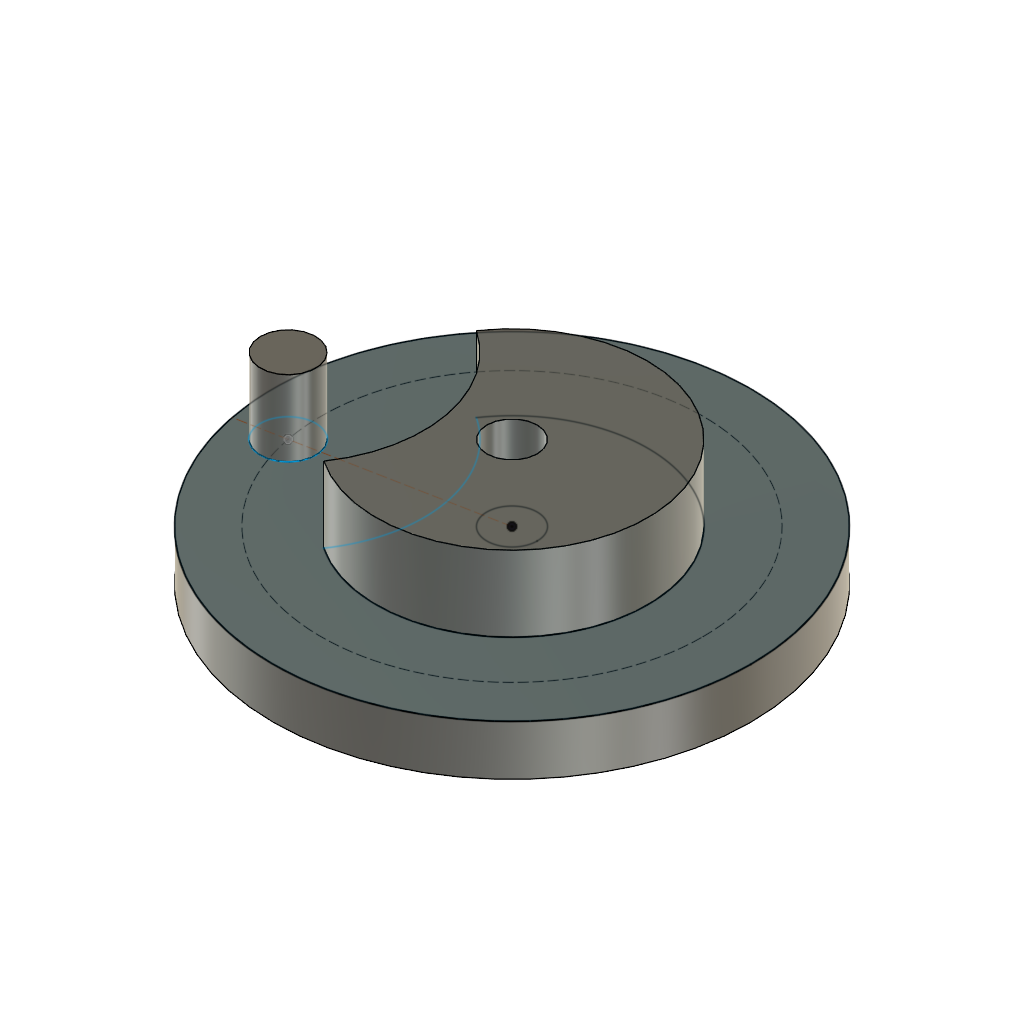
Geneva_Mechanism_Assembly (Autodesk Fusion 360 archive; units mm, degrees)
design "Genevamechfina;"
part number: 2026-10-26-18-54-31-183
Autodesk Fusion 360 part; units mm, degrees
sketch "Sketch1" plane through (0, 0, 0) normal (0, 0, 1) x (1, 0, 0)
  circle A0 centre (0, 0) radius 47.5
  line L0 (0, 0) -> (-46.627, -9.0648) construction
  circle A1 centre (0, 0) radius 38 construction
  circle A2 centre (-37.3016, -7.2518) radius 5.5
  arc A3 (-14.9899, -22.4567) -> (-22.3117, 15.2048) centre (-37.3016, -7.2518) ccw
  arc A4 (-14.9899, -22.4567) -> (-22.3117, 15.2048) centre (0, 0) ccw
  circle A5 centre (0, 0) radius 5
  dimension "d1" = 95
  dimension "d2" = 54
  dimension "d4" = 76
  dimension "d5" = 11
  dimension "d6" = 54
  dimension "d7" = 10
  constraint coincident A0.centre L0.start
  constraint concentric A0 A4
  constraint coincident A0 L0.end
  constraint coincident A1 A2.centre
  constraint coincident L0 A2.centre
  constraint concentric A2 A3
  constraint concentric A0 A5
  measures "d1" diameter of A0
  measures "d2" diameter of A4
  measures "d4" diameter of A1
  measures "d5" diameter of A2
  measures "d6" diameter of A3
  measures "d7" diameter of A5
extrude "Extrude1" add sketch "Sketch1" along normal blind 15 contours A2 | A3 A4 makes body 1 at (-31.829, -7.7995, 10) makes body 2 at (-8.8966, 25.4922, 10)
extrude "Extrude2" add sketch "Sketch1" against normal blind 10 contours A0 | A2 | A3 A4 bodies 1 2
